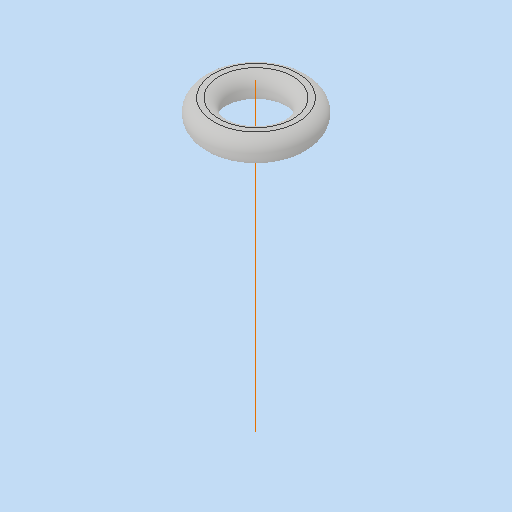
# Autodesk Inventor part: MM0868AN230_G02_110
Saved by Autodesk Inventor 2023.3 (Build 273359000, 359)
## iProperties
RuleStatus: InUse
Created: 2020-11-20
Part Number: MM0868AN230_G02_110
Material: Generisch
Description: =<RBPARTNOTITLE2>
Document SubType Name: Modeling
Designer: Anwendungsoptionen User eintragen
Mass: 0.0649189 g
Surface Area: 0.295836 cm^2
Volume: 0.00737715 cm^3
Density: 8.8 g/cm^3
Appearance: Vorgabe
Vendor: Bosch Rexroth
AnP_Kategorie: 2
AnP_Material: =<Material>
AnP_TemplVers: 20200821
RBDOCUMENTTYPE: DRF
RBDOCUMENTVERSION: 00
RBDRAWINGMAINSCALE: 1:1
RBDRAWINGMISSINGSPEC: --
RBDRAWINGVOLUME: --
RBDSV1: 0850
RBGBEDGESIN1: +0,5
RBGBEDGESIN2: +0,2
RBGBEDGESOUT1: -0,3
RBGBEDGESOUT2: -0,1
RBGBREMARKSINDEX: E
RBMATERIAL: --
RBMATMEETS: --
RBMATNO: =<Part Number>
RBPARTMADEOF: R341111801
RBPARTNO: SIEHE MNR
RBPARTNOTITLE1: O-RING DIN3771-3X1-N-NBR70
RBPARTNOTITLE2: O-RING DIN3771-3X1-N-NBR70
RBPARTSAFETYINDICATOR: --
RBSURFACE: --
RBSURFACE2: --
RBZEDGESNORM: ISO13715:2002-06
RBZGENDIMCLASS: m
RBZGENDIMNORM: ISO 2768-1:1989-11
RBZGENGEOCLASS: H
RBZGENGEONORM: ISO 2768-2:1989-11
RBZSURFACENORM: ISO13D2:2002-02
RBZTOLERANCENORM: ISO 14405-1:2010-12
Author: Anwendungsoptionen User eintragen
Keywords: =<RBPARTMADEOF>
Comments: =<RBSURFACE2>
Revision Number: 01
Autodesk Inventor part; units mm, degrees
ref_plane "YZ Plane" through (0, 0, 0) normal (1, 0, 0) x (0, 1, 0)
ref_plane "XZ Plane" through (0, 0, 0) normal (0, 1, 0) x (-1, 0, 0)
ref_plane "XY Plane" through (0, 0, 0) normal (0, 0, 1) x (1, 0, 0)
sketch "Skizze1" plane through (0, 0, 0) normal (0, 0, 1) x (1, 0, 0)
  circle A0 centre (1.5, 0) radius 0.5
  line L0 (0, 0.7) -> (0, -0.7) projected
  line L1 (-0.4, 0) -> (2.4, 0) projected
  line L2 (1.4005, 0.49) -> (1.5995, 0.49)
  line L3 (1.5995, -0.49) -> (1.4005, -0.49)
  point P0 (0, 0)
  dimension "d0" = 1
  dimension "d1" = 1.5
  dimension "d3" = 0.98
  constraints: 4 end point, 4 point on circle, 2 horizontal, 1 centre point, 1 point on line, 1 other
  measures "d0" diameter of A0
  measures "d1" distance of A0.centre point (0, 0)
  measures "d3" distance between parallel lines of L3 L2
revolve "Umdrehung1" add sketch "Skizze1" angle 360 about axis through (0, 0, 0) along (0, -1, 0) contours L1 A0 L2 | A0 L3 L1
